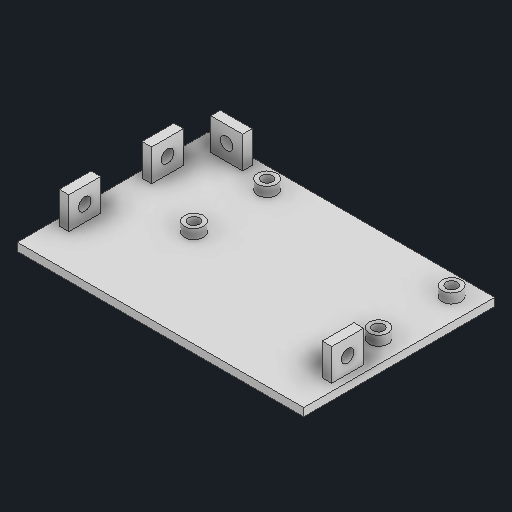
# Autodesk Inventor part: base_plate
Saved by Autodesk Inventor 2027.1 (Build 311270010, 270A)
## iProperties
Created: 2026-10-29
Part Number: base_plate
Material: Generic
Document SubType Name: Modeling
Designer: alexg
Density: 1 g/cm^3
Appearance: Default
Author: alexg
Autodesk Inventor part; units mm, degrees
ref_plane "Work Plane1" through (0, -84.37, 0) normal (0, 1, 0) x (-1, 0, 0)
sketch "Plate sketch" plane through (0, -84.37, 0) normal (0, 1, 0) x (-1, 0, 0)
  line L0 (45, -30) -> (-45, -30)
  line L1 (-45, -30) -> (-45, 30)
  line L2 (-45, 30) -> (45, 30)
  line L3 (45, 30) -> (45, -30)
  constraints: 8 end point, 2 parallel, 1 horizontal, 1 perpendicular
extrude "Plate" add sketch "Plate sketch" against normal blind 2.5
ref_plane "Work Plane2" through (0, -84.37, 0) normal (0, 1, 0) x (-1, 0, 0)
sketch "Pi standoffs sketch" plane through (0, -84.37, 0) normal (0, 1, 0) x (-1, 0, 0)
  circle A0 centre (-37.97, -23.52) radius 3
  circle A1 centre (20.03, -23.52) radius 3
  circle A2 centre (-37.97, -0.52) radius 3
  circle A3 centre (20.03, -0.52) radius 3
  constraints: 4 centre point
extrude "Pi standoffs" add sketch "Pi standoffs sketch" along normal blind 3
ref_plane "Work Plane3" through (0, -81.37, 0) normal (0, 1, 0) x (-1, 0, 0)
sketch "M2.5 insert holes sketch" plane through (0, -81.37, 0) normal (0, 1, 0) x (-1, 0, 0)
  circle A0 centre (-37.97, -23.52) radius 1.75
  circle A1 centre (20.03, -23.52) radius 1.75
  circle A2 centre (-37.97, -0.52) radius 1.75
  circle A3 centre (20.03, -0.52) radius 1.75
  constraints: 4 centre point
extrude "M2.5 insert holes" cut sketch "M2.5 insert holes sketch" against normal blind 5
ref_plane "Work Plane4" through (0, -84.37, 0) normal (0, 1, 0) x (-1, 0, 0)
sketch "Screw tabs sketch" plane through (0, -84.37, 0) normal (0, 1, 0) x (-1, 0, 0)
  line L0 (42.8, -17) -> (39.8, -17)
  line L1 (39.8, -17) -> (39.8, -7)
  line L2 (39.8, -7) -> (42.8, -7)
  line L3 (42.8, -7) -> (42.8, -17)
  line L4 (42.8, 9) -> (39.8, 9)
  line L5 (39.8, 9) -> (39.8, 19)
  line L6 (39.8, 19) -> (42.8, 19)
  line L7 (42.8, 19) -> (42.8, 9)
  line L8 (-39.8, 9) -> (-42.8, 9)
  line L9 (-42.8, 9) -> (-42.8, 19)
  line L10 (-42.8, 19) -> (-39.8, 19)
  line L11 (-39.8, 19) -> (-39.8, 9)
  line L12 (39, -27.8) -> (29, -27.8)
  line L13 (29, -27.8) -> (29, -24.8)
  line L14 (29, -24.8) -> (39, -24.8)
  line L15 (39, -24.8) -> (39, -27.8)
  constraints: 32 end point, 8 parallel, 4 horizontal, 4 perpendicular
extrude "Screw tabs" add sketch "Screw tabs sketch" along normal blind 10
ref_plane "Work Plane5" through (-43.5, 0, 0) normal (1, 0, 0) x (0, 1, 0)
sketch "M3 insert holes L sketch" plane through (-43.5, 0, 0) normal (1, 0, 0) x (0, 1, 0)
  circle A0 centre (-79.37, -12) radius 2
  circle A1 centre (-79.37, 14) radius 2
  constraints: 2 centre point
extrude "M3 insert holes L" cut sketch "M3 insert holes L sketch" along normal blind 4
ref_plane "Work Plane6" through (43.5, 0, 0) normal (1, 0, 0) x (0, 1, 0)
sketch "M3 insert holes R sketch" plane through (43.5, 0, 0) normal (1, 0, 0) x (0, 1, 0)
  circle A0 centre (-79.37, 14) radius 2
  constraints: 1 centre point
extrude "M3 insert holes R" cut sketch "M3 insert holes R sketch" against normal blind 4
ref_plane "Work Plane7" through (0, 0, -28.5) normal (0, 0, 1) x (1, 0, 0)
sketch "M3 insert hole B sketch" plane through (0, 0, -28.5) normal (0, 0, 1) x (1, 0, 0)
  circle A0 centre (-34, -79.37) radius 2
  constraints: 1 centre point
extrude "M3 insert hole B" cut sketch "M3 insert hole B sketch" along normal blind 4
body "Solid1"
